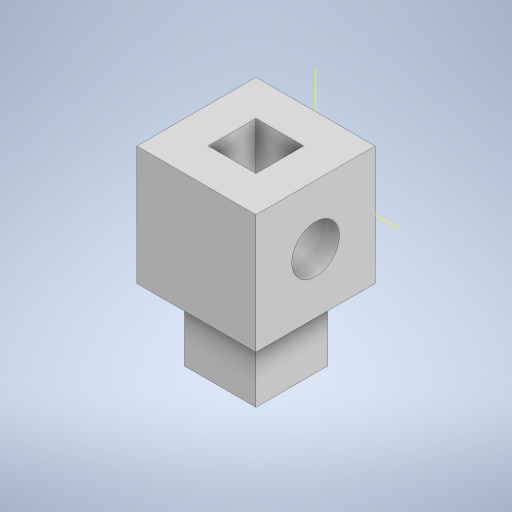
# Autodesk Inventor part: vysunutí
Saved by Autodesk Inventor 2024 (Build 280153000, 153)
## iProperties
Created: 2025-01-28
Part Number: vysunutí
Material: Všeobecné
Document SubType Name: Modeling
Designer: zak
Density: 1 g/cm^3
Appearance: Výchozí
Author: zak
Autodesk Inventor part; units mm, degrees
ref_plane "YZ Plane" through (0, 0, 0) normal (1, 0, 0) x (0, 1, 0)
ref_plane "XZ Plane" through (0, 0, 0) normal (0, 1, 0) x (-1, 0, 0)
ref_plane "XY Plane" through (0, 0, 0) normal (0, 0, 1) x (1, 0, 0)
sketch "Náčrt1" plane through (0, 0, 0) normal (0, 0, 1) x (1, 0, 0)
  line L0 (-35, 0) -> (35, 0) projected
  line L1 (0, 35) -> (0, -35) projected
  line L2 (-25, 25) -> (25, 25)
  line L3 (25, 25) -> (25, -25)
  line L4 (25, -25) -> (-25, -25)
  line L5 (-25, -25) -> (-25, 25)
  point P0 (0, 0)
  dimension "d0" = 50
  dimension "d1" = 50
  dimension "d2" = 25
  constraints: 8 end point, 2 parallel, 1 horizontal, 1 perpendicular, 1 other
  measures "d0" distance of L2.start L2.end
  measures "d1" distance of L2.end L3.end
  measures "d2" distance between parallel lines of L1 L5
extrude "Vysunutí1" add sketch "Náčrt1" along normal mid plane 50
sketch "Náčrt2" plane through (-25, -25, 25) normal (0, -1, 0) x (1, 0, 0)
  line L0 (25, 10) -> (25, -60) projected
  line L1 (-10, -25) -> (60, -25) projected
  line L2 (10, -10) -> (40, -10)
  line L3 (40, -10) -> (40, -40)
  line L4 (40, -40) -> (10, -40)
  line L5 (10, -40) -> (10, -10)
  point P0 (25, -25)
  dimension "d6" = 30
  dimension "d7" = 30
  dimension "d8" = 15
  constraints: 8 end point, 2 parallel, 1 horizontal, 1 perpendicular, 1 other
  measures "d6" distance of L2.start L2.end
  measures "d7" distance of L2.end L3.end
  measures "d8" distance between parallel lines of L0 L5
sketch "Náčrt3" plane through (-25, -25, 25) normal (0, -1, 0) x (1, 0, 0)
  point P0 (25, -25)
extrude "Vysunutí2" add sketch "Náčrt2" along normal blind 30
sketch "Náčrt4" plane through (-25, -55, 25) normal (0, -1, 0) x (1, 0, 0)
  line L0 (25, 10) -> (25, -60) projected
  line L1 (-10, -25) -> (60, -25) projected
  line L2 (15, -35) -> (35, -35)
  line L3 (35, -35) -> (35, -15)
  line L4 (35, -15) -> (15, -15)
  line L5 (15, -15) -> (15, -35)
  point P0 (25, -25)
  dimension "d12" = 20
  dimension "d13" = 20
  constraints: 8 end point, 2 parallel, 1 horizontal, 1 perpendicular, 2 other
  measures "d12" distance of L4.end L3.end
  measures "d13" distance of L3.end L2.end
extrude "Vysunutí3" cut sketch "Náčrt4" against normal through all
sketch "Náčrt5" plane through (15, -25, -15) normal (0, 0, -1) x (-1, 0, 0)
  line L0 (-20, 25) -> (50, 25) projected
  line L1 (15, -46) -> (15, 66) projected
  line L2 (25, -30) -> (25, 50) projected
  line L3 (5, -30) -> (5, 50) projected
  line L4 (25, -5) -> (5, -5)
  line L5 (5, -5) -> (5, -25)
  line L6 (5, -25) -> (25, -25)
  line L7 (25, -25) -> (25, -5)
  point P0 (15, 25)
  point P1 (25, -25)
  point P2 (5, -5)
  dimension "d16" = 20
  dimension "d17" = 5
  constraints: 8 end point, 2 parallel, 2 point on line, 1 horizontal, 1 perpendicular
  measures "d16" distance of L6.end L4.start
  measures "d17" distance of L2.start L6.end
extrude "Vysunutí4" cut sketch "Náčrt5" against normal up to surface (5 mm away) contours L4 L1 L6 L3 | L4 L2 L6 L1
sketch "Náčrt6" plane through (0, 0, -25) normal (0, 0, -1) x (-1, 0, 0)
  line L0 (-35, 0) -> (35, 0) projected
  line L1 (0, -71) -> (0, 41) projected
  point P0 (0, 0)
sketch "Náčrt7" plane through (25, -25, 25) normal (1, 0, 0) x (0, 0, -1)
  line L0 (-10, 25) -> (60, 25) projected
  line L1 (25, -46) -> (25, 66) projected
  point P0 (25, 25)
  point P1 (25, 25)
  constraints: 1 coincident
hole "Díra1" at (25, 0, 0) direction (-1, 0, 0) diameter 20 depth 35
equation "\"d1\" = d0"
equation "\"d2\" = 0.5 * d0"
equation "\"d4\" = d0"
equation "\"d7\" = d6"
equation "\"d8\" = 0.5 * d6"
equation "\"d9\" = d6"
